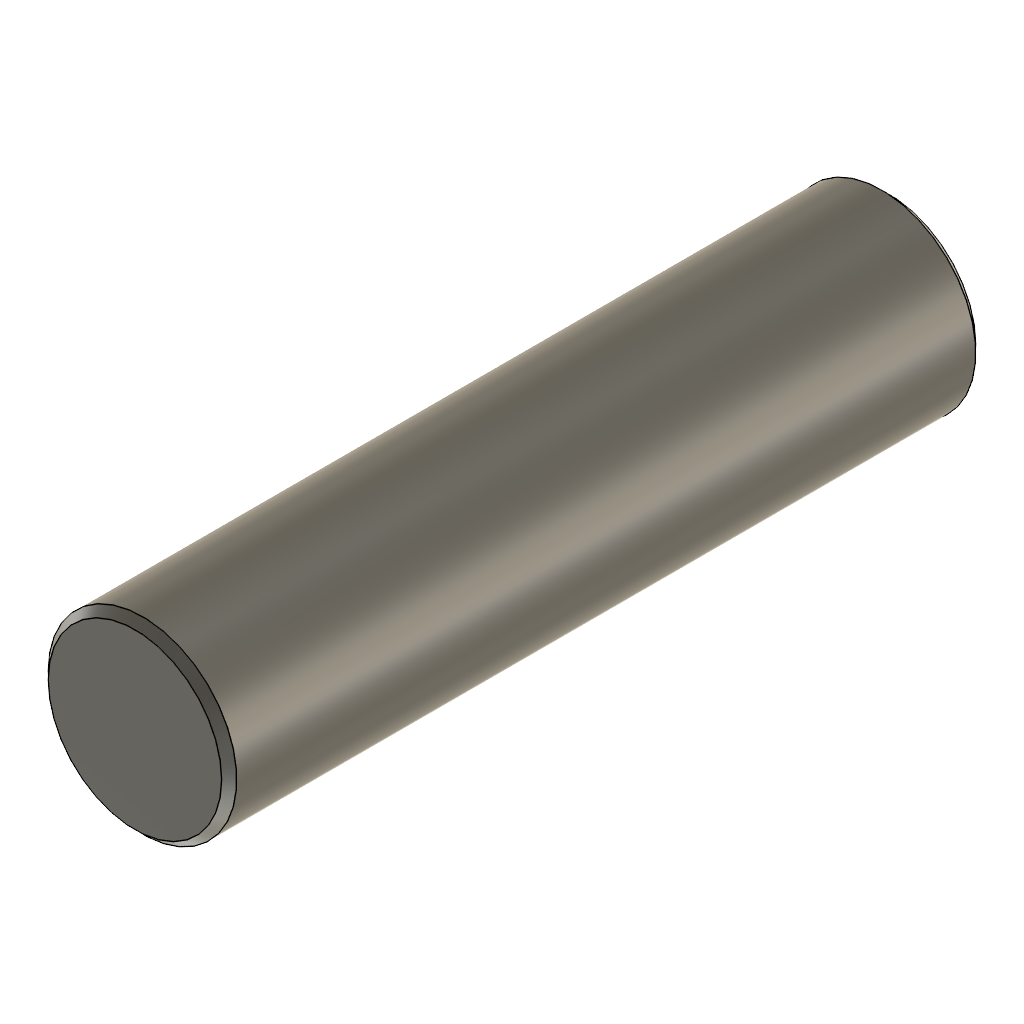
Shaft_GearReduction (Autodesk Fusion 360 design; units mm, degrees)
part number: 2026-10-29-00-37-00-818
Autodesk Fusion 360 part; units mm, degrees
sketch "Sketch1" plane through (0, 0, 0) normal (0, 1, 0) x (1, 0, 0)
  circle A0 centre (0, 0) radius 3.175
  dimension "d1" = 6.35
  constraint coincident A0.centre origin
  measures "d1" diameter of A0
extrude "Extrude1" add sketch "Sketch1" along normal blind 25.4
chamfer "Chamfer1" distance 0.254 angle 45 2 edges at (-2.9601, 0, 1.1481) (-2.9601, 25.4, 1.1481) tangent chain off
